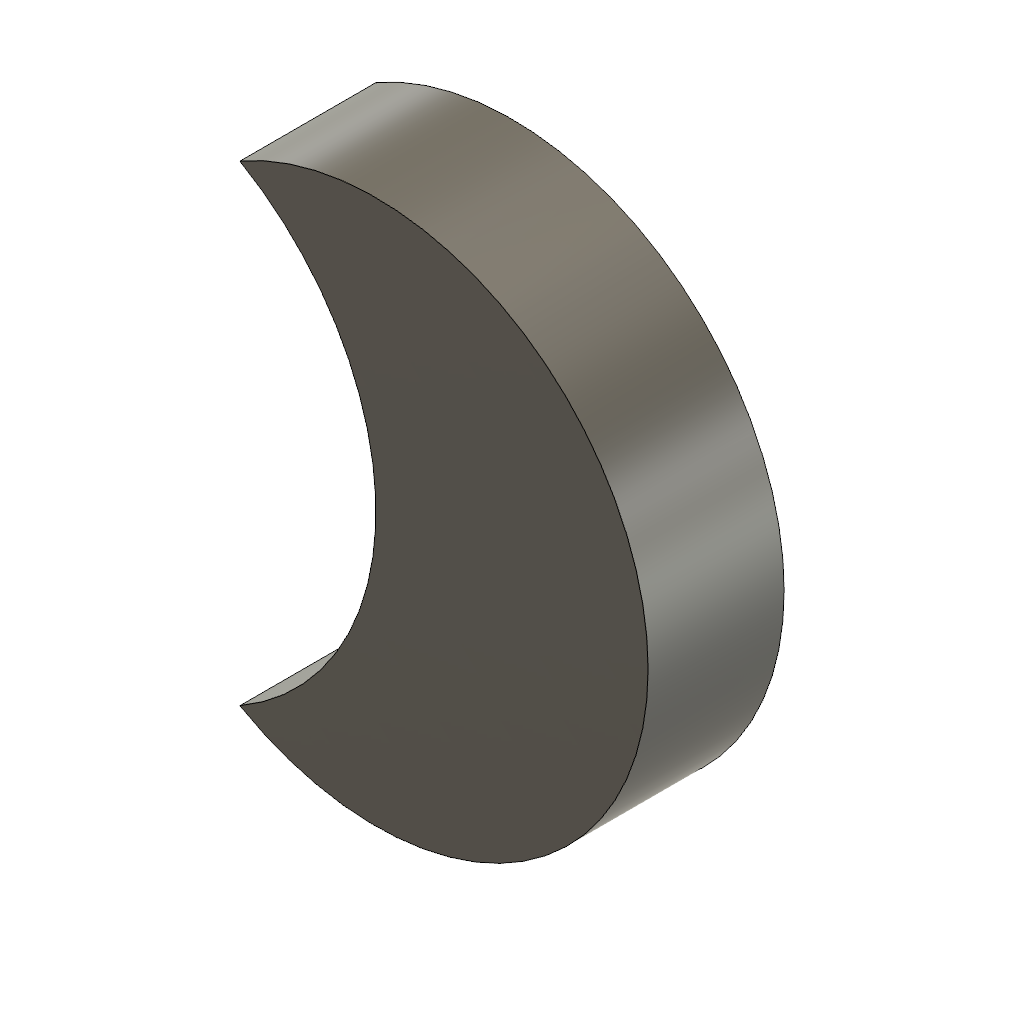
circle_right_complement (Autodesk Fusion 360 design; units mm, degrees)
part number: 2026-10-21-11-21-44-190
Autodesk Fusion 360 part; units mm, degrees
sketch "TrimmedProfileSources" plane through (0, 0, 0) normal (0, 0, 1) x (1, 0, 0)
  circle A0 centre (-10, 0) radius 20
  circle A1 centre (10, 0) radius 20
extrude "SelectedTrimmedProfile" add sketch "TrimmedProfileSources" along normal blind 10 contours A0 A1 picked at (22.9627, -2.9586)
